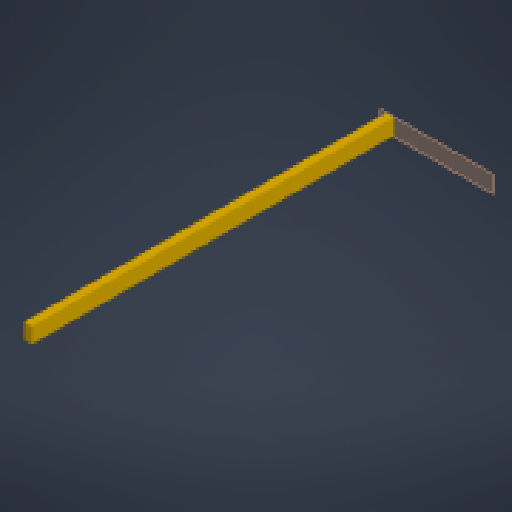
# Autodesk Inventor part: 2x4x90
Saved by Autodesk Inventor 2027 (Build 310192000, 192)
## iProperties
Created: 2026-08-07
Part Number: 2x4x90
Material: Generic
Document SubType Name: Modeling
Designer: lucas
Density: 1 g/cm^3
Appearance: Default
Author: lucas
Autodesk Inventor part; units mm, degrees
ref_plane "YZ Plane" through (0, 0, 0) normal (1, 0, 0) x (0, 1, 0)
ref_plane "XZ Plane" through (0, 0, 0) normal (0, 1, 0) x (-1, 0, 0)
ref_plane "XY Plane" through (0, 0, 0) normal (0, 0, 1) x (1, 0, 0)
ref_plane "Work Plane1" through (0, 811.1398, 0) normal (0, 0, 1) x (1, 0, 0)
sketch "Sketch1" plane through (0, 811.1398, 0) normal (0, 0, 1) x (1, 0, 0)
  line L0 (-330.2, -50.8) -> (-292.1, -50.8)
  line L1 (-292.1, -50.8) -> (-292.1, 38.1)
  line L2 (-292.1, 38.1) -> (-330.2, 38.1)
  line L3 (-330.2, 38.1) -> (-330.2, -50.8)
  point P0 (0, -811.1398)
  dimension "d0" = 88.9
  dimension "d1" = 38.1
  constraints: 8 end point, 2 parallel, 1 horizontal, 1 perpendicular, 1 other
  measures "d0" distance of L0.end L1.end
  measures "d1" distance of L1.end L2.end
extrude "Extrusion1" add sketch "Sketch1" along normal blind 2336.8
body "Solid1"
